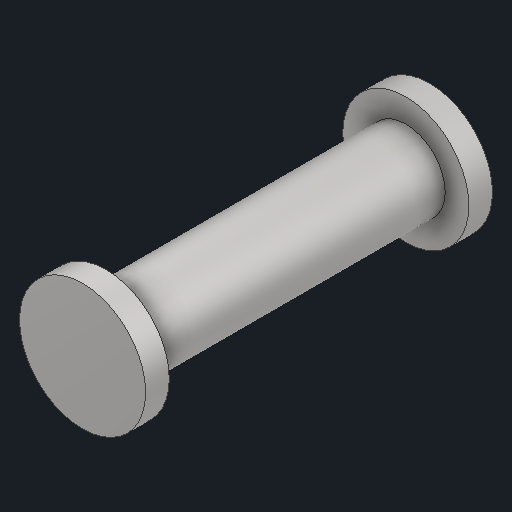
# Autodesk Inventor part: tripod_brace_pin
Saved by Autodesk Inventor 2027.1 (Build 311270010, 270A)
## iProperties
Created: 2026-11-04
Part Number: tripod_brace_pin
Material: Generic
Description: Brace hinge pin
Document SubType Name: Modeling
Designer: Claude (from photos)
Density: 1 g/cm^3
Appearance: Stainless - Satin
Author: alexg
Autodesk Inventor part; units mm, degrees
ref_plane "Work Plane1" through (0, 0, -9.5) normal (0, 0, 1) x (1, 0, 0)
sketch "Pin sketch" plane through (0, 0, -9.5) normal (0, 0, 1) x (1, 0, 0)
  circle A0 centre (-40.5553, -199.1388) radius 2.5
  constraints: 1 centre point
extrude "Pin" add sketch "Pin sketch" along normal blind 19
ref_plane "Work Plane2" through (0, 0, 9.5) normal (0, 0, 1) x (1, 0, 0)
sketch "Head sketch" plane through (0, 0, 9.5) normal (0, 0, 1) x (1, 0, 0)
  circle A0 centre (-40.5553, -199.1388) radius 4
  constraints: 1 centre point
extrude "Head" add sketch "Head sketch" along normal blind 1.5
ref_plane "Work Plane3" through (0, 0, -9.5) normal (0, 0, 1) x (1, 0, 0)
sketch "Head 2 sketch" plane through (0, 0, -9.5) normal (0, 0, 1) x (1, 0, 0)
  circle A0 centre (-40.5553, -199.1388) radius 4
  constraints: 1 centre point
extrude "Head 2" add sketch "Head 2 sketch" against normal blind 1.5
body "Solid1"
